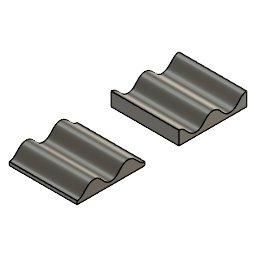
mould basic ridges v2 cleaned up (Autodesk Fusion 360 design; units mm, degrees)
part number: 2026-06-01-15-53-17-386
Autodesk Fusion 360 part; units mm, degrees
sketch "Sketch3" plane through (0, 0, 0) normal (1, 0, 0) x (0, 1, 0)
  spline S0 degree 5 poles (0, 0) (1.1772, 0) (3.4048, 0.3001) (6.3673, 1.6507) (9.7426, 4.9627) (13.9662, 10.0373) (18.9393, 14.1773) (25.064, 15.7986) (30.9233, 14.1773) (35.3862, 10.0373) (39.4218, 4.9627) (43.9948, 0.8227) (50, -0.7986) (56.0052, 0.8227) (60.5782, 4.9627) (64.6138, 10.0373) (69.0767, 14.1773) (74.936, 15.7986) (81.0607, 14.1773) (86.0338, 10.0373) (90.2574, 4.9627) (93.6327, 1.6507) (96.5952, 0.3001) (98.8228, 0) (100, 0) knots 0 0 0 0 0 0 0.05 0.1 0.15 0.2 0.25 0.3 0.35 0.4 0.45 0.5 0.55 0.6 0.65 0.7 0.75 0.8 0.85 0.9 0.95 1 1 1 1 1 1
  line L0 (65, 15) -> (85, 15)
  line L1 (15, 15) -> (35, 15)
  line L2 (-10, 0) -> (10, 0)
  line L3 (90, 0) -> (110, 0)
  line L4 (0, -5) -> (100, -5)
  line L5 (100, -5) -> (100, 0)
  line L6 (0, 0) -> (0, -5)
  line L7 (40, 0) -> (60, 0)
  line L8 (1.75, 0) -> (22.5, 0)
  line L9 (100, 0) -> (100, 20)
  line L10 (100, 20) -> (0, 20)
  line L11 (0, 20) -> (0, 0)
  point P0 (25, 15)
  point P1 (50, 0)
  point P2 (75, 15)
  dimension "d9" = 100
  dimension "d10" = 5
  dimension "d12" = 50
  dimension "wave_width" = 50
  dimension "d14" = 50
  dimension "d15" = 20
  dimension "d16" = 25
  dimension "d18" = 5
  dimension "wave_height" = 15
  constraint coincident S0.start L6.start
  constraint midpoint P2 L0
  constraint midpoint P0 L1
  constraint midpoint S0.start L2
  constraint midpoint S0.end L3
  constraint parallel L2 L4
  constraint perpendicular L4 L6
  constraint midpoint P1 L7
  constraint horizontal L1
  constraint horizontal L0
  constraint horizontal L3
  constraint horizontal L7
  constraint horizontal L2
  constraint coincident P1 L8
  constraint coincident S0.end L8
  constraint equal L0 L3
  constraint equal L0 L7
  constraint equal L1 L7
  constraint equal L1 L2
  constraint horizontal P0 P2
  constraint perpendicular L3 L9
  constraint perpendicular L9 L10
  constraint perpendicular L2 L11
  measures "d9" distance of L4.start L4.end
  measures "d10" distance of S0.end L4.end
  measures "d12" horizontal distance of P0 P2
  measures "wave_width" distance of S0.start P1
  measures "d14" distance of S0.end P1
  measures "d15" distance of L3.start L3.end
  measures "d16" distance of S0.start P0
  measures "d18" distance of P2 L10
  measures "wave_height" distance of S0.end P2
extrude "Extrude1" add sketch "Sketch3" along normal blind 100 contours S0 L4 L5 L6 makes body 1
extrude "Extrude5" add sketch "Sketch3" along normal up to surface (100 mm away) separate body contours S0 L9 L10 L11 makes body 2
move_body "Move3" bodies 2 to x (1, 0, 0) y (0, -1, 0) z (0, 0, -1) at (0, 250, 15)
equation "d12 = wave_width"
equation "d14 = wave_width"
equation "d16 = wave_width / 2"
equation "d18 = d10"
